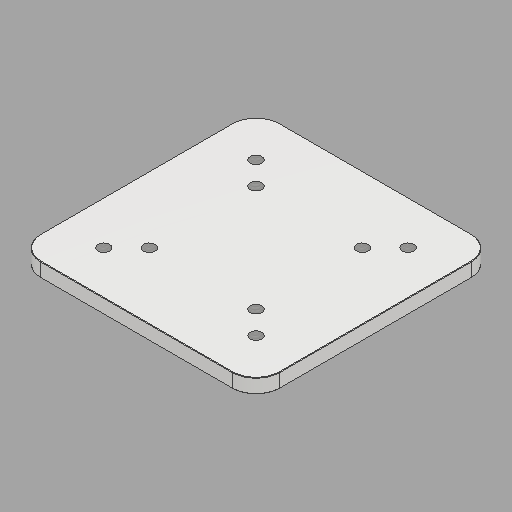
# Autodesk Inventor part: BT022_thutrn22_26
Saved by Autodesk Inventor 2025.3 (Build 293356000, 356)
## iProperties
Company: HTBLA Kaindorf
RuleStatus: InUse
Created: 2026-08-19
Part Number: BT022_thutrn22_26
Project: Biegeroboter
Material: ABS-Kunststoff
Description: gehaeuse_deckel_motor_v3
Document SubType Name: Modeling
Designer: thutrn22
Density: 1.06 g/cm^3
Appearance: Glatt - Weiß
Mass: 62.0717 g
Surface Area: 224.732 cm^2
Volume: 58.5582 cm^3
AfterDocNew0: iProperties-Editor_aufrufen
Author: trist
Keywords: 2026
Autodesk Inventor part; units mm, degrees
ref_plane "YZ Plane" through (0, 0, 0) normal (1, 0, 0) x (0, 1, 0)
ref_plane "XZ Plane" through (0, 0, 0) normal (0, 1, 0) x (-1, 0, 0)
ref_plane "XY Plane" through (0, 0, 0) normal (0, 0, 1) x (1, 0, 0)
sketch "Skizze3" plane through (0, 0, 0) normal (0, 0, 1) x (1, 0, 0)
  line L0 (-70, 0) -> (70, 0) projected
  line L1 (0, -70) -> (0, 70) projected
  line L2 (-50, 50) -> (50, 50)
  line L3 (50, 50) -> (50, -50)
  line L4 (50, -50) -> (-50, -50)
  line L5 (-50, -50) -> (-50, 50)
  circle A0 centre (31.82, 31.82) radius 3
  circle A1 centre (-31.82, 31.82) radius 3
  circle A2 centre (31.82, -31.82) radius 3
  circle A3 centre (-31.82, -31.82) radius 3
  point P0 (0, 0)
  point P1 (22.274, 22.274)
  point P2 (-22.274, 22.274)
  point P3 (22.274, -22.274)
  point P4 (-22.274, -22.274)
  dimension "d4" = 100
  dimension "d5" = 100
  dimension "d6" = 6
  dimension "d7" = 63.64
  dimension "d8" = 63.64
  dimension "d9" = 22.274
  dimension "d10" = 22.274
  constraints: 8 end point, 6 symmetric about line, 4 centre point, 4 coincident, 2 parallel, 1 horizontal, 1 perpendicular, 5 other
  measures "d4" distance of L3.end L4.end
  measures "d5" distance of L2.end L3.end
  measures "d6" diameter of A0
  measures "d7" distance of A0.centre A1.centre
  measures "d8" distance of A2.centre A0.centre
  measures "d9" distance from line of L0 point (22.274, 22.274)
  measures "d10" distance from line of L1 point (22.274, 22.274)
extrude "Extrusion3" add sketch "Skizze3" along normal blind 6 contours L5 L2 L1 L0 | L0 L1 L4 L5 | L1 L2 L3 L0 | L0 L3 L4 L1 | A0 | A1 | A2 | A3
fillet "Rundung1" radius 10 4 edges at (50, 50, 3) (50, -50, 3) (-50, -50, 3) (-50, 50, 3)
hole "Bohrung1" at (22.274, 22.274, 0) at (-22.274, 22.274, 0) at (-22.274, -22.274, 0) at (22.274, -22.274, 0) direction (0, 0, 1) diameter 4.917 end through all thread size "M6x1" class "6H" standard "ISO Metric profile"
chamfer "Fasen1" distance 0.2 angle 45 16 edges at (50, 0, 6) (47.0711, 47.0711, 6) (0, 50, 6) (-47.0711, 47.0711, 6) (-50, 0, 6) (-47.0711, -47.0711, 6) (0, -50, 6) (47.0711, -47.0711, 6) (50, 0, 0) (47.0711, 47.0711, 0) (0, 50, 0) (-47.0711, 47.0711, 0) (-50, 0, 0) (-47.0711, -47.0711, 0) (0, -50, 0) (47.0711, -47.0711, 0)
hole "Bohrung2" at (-31.82, -31.82, 0) at (-31.82, 31.82, 0) at (31.82, 31.82, 0) at (31.82, -31.82, 0) direction (0, 0, 1) diameter 4.917 end through all thread size "M6x1" class "6H" standard "ISO Metric profile"
equation "\"d11\" = d6"
